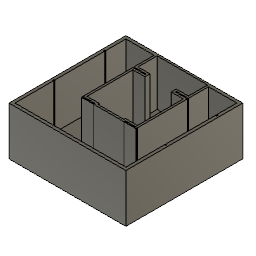
umaze_wbr (Autodesk Fusion 360 design; units mm, degrees)
Autodesk Fusion 360 part; units mm, degrees
sketch "草图1" plane through (0, 0, 0) normal (0, 0, 1) x (1, 0, 0)
  line L0 (0, 0) -> (110, 0)
  line L1 (110, 0) -> (110, 110)
  line L2 (110, 110) -> (0, 110)
  line L3 (0, 110) -> (0, 0)
  line L4 (28, 110) -> (82, 110)
  line L5 (82, 110) -> (82, 38)
  line L6 (82, 38) -> (28, 38)
  line L7 (28, 38) -> (28, 110)
  point P0 (55, 110)
  point P1 (55, 110)
  dimension "d1" = 110
  dimension "d2" = 110
  dimension "d6" = 54
  dimension "d7" = 72
  constraint horizontal L0
  constraint vertical L1
  constraint horizontal L2
  constraint vertical L3
  constraint coincident L0.start L3.end
  constraint coincident L2 P1
  constraint midpoint L2 P1
  constraint horizontal L4
  constraint vertical L5
  constraint horizontal L6
  constraint vertical L7
  constraint coincident L2 L4.start
  constraint coincident L4 P1
  constraint midpoint L4 P1
  constraint coincident P1 P0
  measures "d1" distance of L0.start L0.end
  measures "d2" distance of L0.start L2.end
  measures "d6" distance of L4.start L4.end
  measures "d7" distance of L4.start L6.end
extrude "拉伸1" add sketch "草图1" along normal blind 45 makes body 1
shell "抽壳1" thickness 3 outward yes removed faces 1 at (64, 36.6667, 45) on bodies 1
extrude "拉伸2" add sketch "草图1" along normal blind 45 separate body contours L2 L4 L5 L6 L7 makes body 2
combine "合并1" operation add target body 1 tool bodies 2
sketch "草图3" plane through (0, 0, 45) normal (0, 0, 1) x (-1, 0, 0)
  line L0 (0, -110) -> (-28, -110)
  line L1 (-28, -110) -> (-28, -38)
  line L2 (-28, -38) -> (-82, -38)
  line L3 (-82, -38) -> (-82, -110)
  line L4 (-82, -110) -> (-110, -110)
  line L5 (-110, -110) -> (-110, 0)
  line L6 (-110, 0) -> (0, 0)
  line L7 (0, 0) -> (0, -110)
  line L8 (3, -113) -> (3, 3)
  line L9 (3, 3) -> (-113, 3)
  line L10 (-113, 3) -> (-113, -113)
  line L11 (-113, -113) -> (3, -113)
  line L12 (0, -110) -> (0, -90)
  line L13 (-55, -113) -> (-55, -38)
  line L14 (0, -90, 0) -> (0, -90, -1)
  line L15 (0, -90) -> (1, -90)
  line L16 (1, -90) -> (1, -89)
  line L17 (1, -89) -> (0, -89)
  line L18 (0, -89) -> (0, -90)
  line L19 (1, -90) -> (-40, -90)
  line L20 (-40, -90) -> (-40, -89)
  line L21 (-40, -89) -> (1, -89)
  line L22 (1, -89) -> (1, -90)
  dimension "d15" = 20
  dimension "d26" = 1
  dimension "d27" = 1
  dimension "d28" = 1
  dimension "d29" = 41
  dimension "d30" = 1
  constraint coincident L0.start L7.end
  constraint coincident L7 L12.end
  constraint midpoint L11 L13.start
  constraint midpoint L2 L13.end
  constraint horizontal L15
  constraint vertical L16
  constraint horizontal L17
  constraint vertical L18
  constraint horizontal L19
  constraint vertical L20
  constraint horizontal L21
  constraint vertical L22
  measures "d15" distance of L0.start L12.end
  measures "d26" distance of L12.end L15.start
  measures "d27" distance of L12.end L15.end
  measures "d28" distance of L12.end L17.end
  measures "d29" distance of L15.end L19.end
  measures "d30" distance of L15.end L16.end
extrude "拉伸3" add sketch "草图3" against normal up to surface (45 mm away) separate body contours L1 L7 L18 L19 L21 | L7 L15 L16 L17 L18 L19 L21 L22 | L1 L19 L20 L21 makes body 3
pattern_linear "R-阵列1" count 2 spacing 50.5 along (0, -1, 0) of bodies 3 makes body 4
ref_plane "工作平面1" through (55, 74, 22.5) normal (1, 0, 0) x (0, 1, 0)
mirror "镜像1" about plane through (55, 74, 22.5) normal (1, 0, 0) of bodies 3 4 makes body 5 at (100.6667, 39.5, 30) makes body 6 at (100.6667, 90, 30)
combine "合并2" operation cut target body 1 tool bodies 3 5 4 6
shell "抽壳2" thickness 2 removed faces 1 at (50, 72.5, 45) on bodies 1
equation "d6 = 110 mm - ( 28 * 2 ) * 1 mm"
